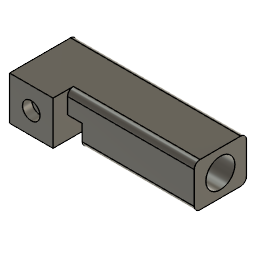
small_connector (Autodesk Fusion 360 design; units mm, degrees)
part number: 2026-05-08-20-33-31-209
Autodesk Fusion 360 part; units mm, degrees
sketch "Sketch1" plane through (0, 0, 0) normal (0, 1, 0) x (1, 0, 0)
  line L0 (-7.5, -7.5) -> (7.5, -7.5)
  line L1 (7.5, -7.5) -> (7.5, 7.5)
  line L2 (7.5, 7.5) -> (-7.5, 7.5)
  line L3 (-7.5, 7.5) -> (-7.5, -7.5)
  line L4 (-7.5, -7.5) -> (7.5, 7.5) construction
  line L5 (7.5, -7.5) -> (-7.5, 7.5) construction
  circle A0 centre (0, 0) radius 3
  dimension "d1" = 15
  dimension "d2" = 15
  dimension "d3" = 6
  constraint horizontal L0
  constraint perpendicular L0 L1
  constraint parallel L0 L2
  constraint parallel L1 L3
  constraint coincident L4 A0.centre
  constraint coincident L5 A0.centre
  constraint coincident A0.centre origin
  measures "d1" distance of L1.end L2.end
  measures "d2" distance of L0.end L1.end
  measures "d3" diameter of A0
extrude "Extrude1" add sketch "Sketch1" along normal blind 3.2
sketch "Sketch2" plane through (0, 3.2, 0) normal (0, 1, 0) x (-1, 0, 0)
  circle A0 centre (0, 0) radius 3
  line L0 (7.5, -7.5) -> (7.5, 7.5)
  line L1 (7.5, 7.5) -> (-7.5, 7.5)
  line L2 (-7.5, 7.5) -> (-7.5, -7.5)
  line L3 (-7.5, -7.5) -> (7.5, -7.5)
  line L4 (7.5, -7.5) -> (-7.5, -7.5)
  line L5 (-7.5, -7.5) -> (-7.5, 7.5)
  line L6 (-7.5, 7.5) -> (7.5, 7.5)
  line L7 (7.5, 7.5) -> (7.5, -7.5)
  line L8 (7.5, -7.5) -> (-7.5, 7.5) construction
  line L9 (-7.5, -7.5) -> (7.5, 7.5) construction
  dimension "d6" = 15
  dimension "d7" = 15
  constraint horizontal L4
  constraint perpendicular L4 L5
  constraint parallel L4 L6
  constraint parallel L5 L7
  constraint coincident L8 A0.centre
  constraint coincident L9 A0.centre
  constraint coincident A0.centre origin
  measures "d6" distance of L1.end L0.end
  measures "d7" distance of L2.end L1.end
extrude "Extrude2" add sketch "Sketch2" along normal blind 19.8 contours A0 | L0 L1 L2 L3 L4 L5 L6 L7
sketch "Sketch4" plane through (7.5, 0, 0) normal (1, 0, 0) x (0, 1, 0)
  line L0 (0, 7.5) -> (0, -7.5)
  line L1 (0, -7.5) -> (23, -7.5)
  line L2 (23, -7.5) -> (23, 7.5)
  line L3 (23, 7.5) -> (0, 7.5)
  line L4 (23, -7.5) -> (5, -7.5)
  line L5 (5, -7.5) -> (5, 7.5)
  line L6 (5, 7.5) -> (23, 7.5)
  line L7 (23, 7.5) -> (23, -7.5)
  circle A0 centre (14, 0) radius 5
  line L8 (14, 0) -> (14, -7.5)
  line L9 (14, 0) -> (5, 0)
  dimension "d10" = 18
  dimension "d11" = 15
  dimension "d12" = 10
  constraint horizontal L4
  constraint vertical L5
  constraint horizontal L6
  constraint vertical L7
  constraint coincident L1.end L2.start
  constraint coincident A0.centre L8.start
  constraint midpoint L4 L8.end
  constraint midpoint L5 L9.end
  constraint perpendicular L5 L9
  measures "d10" distance of L1.end L4.end
  measures "d11" distance of L1.end L2.end
  measures "d12" diameter of A0
extrude "Extrude3" add sketch "Sketch4" along normal blind 5 contours L1 L2 L3 L4 L5 L6 L7 A0 L8 L9
sketch "Sketch5" plane through (12.5, 0, 0) normal (1, 0, 0) x (0, 1, 0)
  line L0 (14, -5) -> (14, -7.5)
  line L1 (14, -7.5) -> (23, -7.5)
  line L2 (23, -7.5) -> (23, 7.5)
  line L3 (23, 7.5) -> (5, 7.5)
  line L4 (5, 7.5) -> (5, 0)
  line L5 (5, 0) -> (9, 0)
  arc A0 (14, -5) -> (9, 0) centre (14, 0) ccw
  line L6 (23, -7.5) -> (5, -7.5)
  line L7 (5, -7.5) -> (5, 7.5)
  line L8 (5, 7.5) -> (23, 7.5)
  line L9 (23, 7.5) -> (23, -7.5)
  circle A1 centre (14, 0) radius 5
  dimension "d15" = 10
  constraint horizontal L6
  constraint vertical L7
  constraint horizontal L8
  constraint vertical L9
  constraint coincident L3.end L4.start
  constraint coincident L1.end L2.start
  constraint concentric A0 A1
  measures "d15" diameter of A1
extrude "Extrude4" add sketch "Sketch5" along normal blind 38.6 contours L0 L1 L2 L3 L4 L5 A0 L6 L7 L8 L9 A1 | L0 L5 L6 L7 A1
fillet "Fillet1" radius 2 1 edges at (21.8, 23, -7.5)
fillet "Fillet2" radius 2 1 edges at (31.8, 5, -7.5)
fillet "Fillet3" radius 2 1 edges at (29.3, 5, 7.5)
fillet "Fillet4" radius 2 1 edges at (21.8, 23, 7.5)
